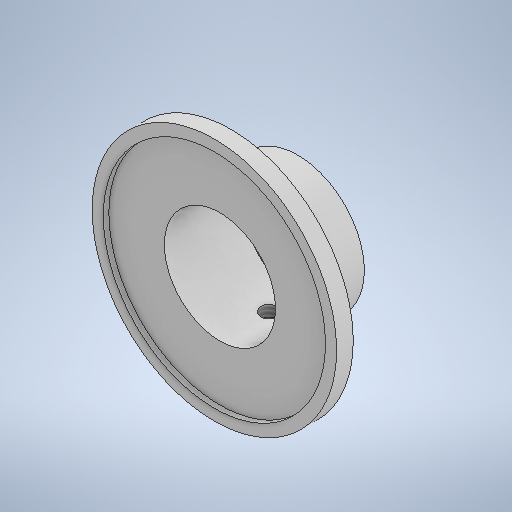
# Autodesk Inventor part: sprzeglo_tył
Saved by Autodesk Inventor 2025.2 (Build 292293000, 293)
## iProperties
Created: 2025-04-06
Part Number: sprzeglo_tył
Material: Ogólny
Document SubType Name: Modeling
Designer: Jan Bołtralik
Density: 1 g/cm^3
Appearance: Domyślna
Author: Jan Bołtralik
Autodesk Inventor part; units mm, degrees
ref_plane "YZ Plane" through (0, 0, 0) normal (1, 0, 0) x (0, 1, 0)
ref_plane "XZ Plane" through (0, 0, 0) normal (0, 1, 0) x (-1, 0, 0)
ref_plane "XY Plane" through (0, 0, 0) normal (0, 0, 1) x (1, 0, 0)
sketch "Szkic1" plane through (0, 0, 0) normal (0, 1, 0) x (-1, 0, 0)
  line L0 (-6.4379, -8.7827) -> (-6.4379, 1.2173)
  line L1 (-1.4379, -8.7827) -> (-1.4379, -1.7827)
  line L2 (-1.4379, -1.7827) -> (3.5621, -1.7827)
  line L3 (3.5621, -1.7827) -> (3.5621, -1.2827)
  line L4 (3.5621, -1.2827) -> (4.5621, -1.2827)
  line L5 (4.5621, -1.2827) -> (4.5621, -2.7827)
  line L6 (4.5621, -2.7827) -> (-0.4379, -2.7827)
  line L7 (-0.4379, -2.7827) -> (-0.4379, -8.7827)
  line L8 (-0.4379, -8.7827) -> (-1.4379, -8.7827)
  point P0 (4.5621, -2.0327)
  dimension "d0" = 10
  dimension "d1" = 7
  dimension "d2" = 10
  dimension "d3" = 12
  dimension "d4" = 20
  dimension "d5" = 22
  dimension "d6" = 6
  dimension "d7" = 0.5
  constraints: 18 end point, 6 perpendicular, 3 vertical, 2 horizontal, 1 midpoint
  measures "d0" distance of L0.start L0.end
  measures "d1" distance of L1.start L1.end
  measures "d2" diameter of L1 L0
  measures "d3" diameter of L7 L0
  measures "d4" diameter of L3 L0
  measures "d5" diameter of point (4.562, -2.033) L0
  measures "d6" distance of L6.end L7.end
  measures "d7" distance of L2.end L3.end
revolve "Obrót1" add sketch "Szkic1" angle 360 about axis through (6.4379, 0, -8.7827) along (0, 0, 1)
sketch "Szkic2" plane through (0, 0, 0) normal (0, 1, 0) x (-1, 0, 0)
  line L0 (-0.4379, -2.7827) -> (-12.4379, -2.7827) projected
  line L1 (-0.4379, -8.7827) -> (-12.4379, -8.7827) projected
  arc A0 (-5.4379, -6.2827) -> (-7.4379, -6.2827) centre (-6.4379, -6.2827) ccw
  line L2 (-7.4379, -6.2827) -> (-7.4379, -8.7827)
  line L3 (-5.4379, -8.7827) -> (-5.4379, -6.2827)
  line L4 (-0.4379, -8.7827) -> (-12.4379, -8.7827) projected
  line L5 (-12.4379, -8.7827) -> (-12.4379, -2.7827) projected
  line L6 (-0.4379, -8.7827) -> (-0.4379, -2.7827) projected
  dimension "d17" = 2.5
  dimension "d18" = 6
  dimension "d19" = 6
  constraints: 4 end point, 2 coincident, 2 point on circle, 2 point on line, 1 centre point, 1 tangent
  measures "d17" distance from line of L1 point (-6.438, -6.283)
  measures "d18" distance from line of L5 point (-6.438, -6.283)
  measures "d19" distance from line of L6 point (-6.438, -6.283)
hole "Hole1" at (6.4379, 0, -6.2827) direction (0, -1, 0) diameter 1.567 end through all thread size "M2x0.4" class "6H" standard "ISO Metric profile"
